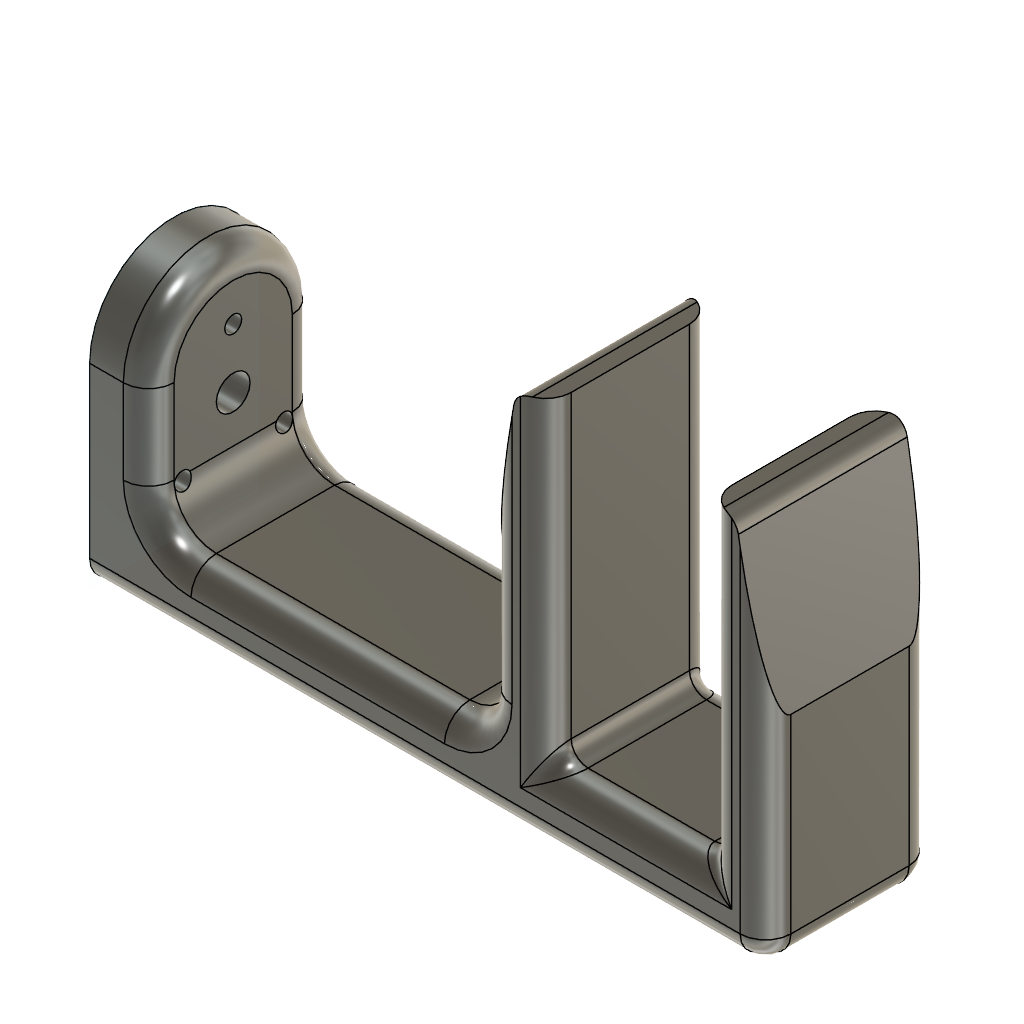
24mce1012_doorstop_model (Autodesk Fusion 360 design; units mm, degrees)
part number: 2026-11-01-15-57-34-278
Autodesk Fusion 360 part; units mm, degrees
sketch "Sketch1" plane through (0, 0, 0) normal (0, 0, 1) x (1, 0, 0)
  line L0 (80, 20) -> (-80, 20)
  line L1 (-80, 20) -> (-80, -20)
  line L2 (-80, -20) -> (80, -20)
  line L3 (80, -20) -> (80, 20)
  line L4 (80, 20) -> (-80, -20) construction
  line L5 (-80, 20) -> (80, -20) construction
  dimension "d1" = 40
  dimension "d2" = 160
  constraint horizontal L0
  constraint perpendicular L0 L1
  constraint parallel L0 L2
  constraint parallel L1 L3
  constraint coincident L4 origin
  constraint coincident L5 origin
  measures "d1" distance of L0.end L1.end
  measures "d2" distance of L0.start L0.end
extrude "Extrude1" add sketch "Sketch1" along normal blind 16
sketch "Sketch2" plane through (-80, 0, 0) normal (-1, 0, 0) x (0, -1, 0)
  line L0 (-20, 0) -> (20, 0)
  line L1 (20, 0) -> (20, 16)
  line L2 (20, 16) -> (-20, 16)
  line L3 (-20, 16) -> (-20, 0)
  line L4 (-20, 16) -> (-20, 46)
  line L5 (-20, 16) -> (20, 16)
  line L6 (20, 16) -> (20, 46)
  arc A0 (20, 46) -> (-20, 46) centre (0, 46) ccw
  dimension "d5" = 30
  constraint coincident L2.end L3.start
  constraint perpendicular L2 L4
  constraint coincident L1.end L2.start
  constraint perpendicular L2 L6
  measures "d5" distance of L2.end L4.end
extrude "Extrude2" add sketch "Sketch2" against normal blind 14 contours L2 L4 L5 L6 A0
sketch "Sketch3" plane through (80, 0, 0) normal (1, 0, 0) x (0, 1, 0)
  line L0 (-20, 0) -> (20, 0)
  line L1 (20, 0) -> (20, 16)
  line L2 (20, 16) -> (-20, 16)
  line L3 (-20, 16) -> (-20, 0)
  line L4 (-20, 16) -> (20, 16)
  line L5 (20, 16) -> (20, 91)
  line L6 (20, 91) -> (-20, 91)
  line L7 (-20, 91) -> (-20, 16)
  dimension "d8" = 75
  constraint coincident L2.end L3.start
  constraint coincident L1.end L2.start
  constraint perpendicular L2 L5
  constraint perpendicular L3 L6
  constraint perpendicular L2 L7
  measures "d8" distance of L1.end L5.end
extrude "Extrude3" add sketch "Sketch3" against normal blind 14 contours L2 L4 L5 L6 L7
sketch "Sketch4" plane through (0, 0, 16) normal (0, 0, 1) x (-1, 0, 0)
  line L0 (-66, 20) -> (-66, -20)
  line L1 (-66, -20) -> (66, -20)
  line L2 (66, -20) -> (66, 20)
  line L3 (66, 20) -> (-66, 20)
  line L4 (-66, -20) -> (-28, -20)
  line L5 (-28, -20) -> (-28, 20)
  line L6 (-28, 20) -> (-14, 20)
  line L7 (-14, 20) -> (-14, -20)
  line L8 (-28, -20) -> (-14, -20)
  dimension "d11" = 38
  dimension "d12" = 14
  constraint coincident L0.end L1.start
  constraint perpendicular L0 L4
  constraint coincident L3 L5.end
  constraint perpendicular L3 L5
  constraint perpendicular L5 L6
  constraint coincident L1 L7.end
  constraint perpendicular L1 L7
  measures "d11" distance of L0.end L4.end
  measures "d12" distance of L5.end L6.end
extrude "Extrude4" add sketch "Sketch4" along normal blind 75 contours L1 L3 L5 L6 L7 L8
sketch "Sketch5" plane through (0, -20, 0) normal (0, -1, 0) x (1, 0, 0)
  line L0 (-80, 0) -> (80, 0)
  line L1 (80, 0) -> (80, 91)
  line L2 (80, 91) -> (66, 91)
  line L3 (66, 91) -> (66, 16)
  line L4 (66, 16) -> (28, 16)
  line L5 (28, 16) -> (28, 91)
  line L6 (28, 91) -> (14, 91)
  line L7 (14, 91) -> (14, 16)
  line L8 (14, 16) -> (-66, 16)
  line L9 (-66, 16) -> (-66, 46)
  line L10 (-66, 46) -> (-80, 46)
  line L11 (-80, 46) -> (-80, 0)
  line L12 (28, 91) -> (21, 91)
  line L13 (21, 91) -> (21, 51)
  line L14 (21, 51) -> (14, 51)
  line L15 (14, 51) -> (21, 91)
  line L16 (21, 51) -> (73, 51)
  line L17 (73, 51) -> (47, 51)
  line L18 (47, 51) -> (47, 80)
  line L19 (80, 51) -> (73, 91)
  line L20 (73, 51) -> (80, 51)
  line L21 (73, 91) -> (73, 51)
  line L22 (47, 51) -> (47, 80)
  constraint coincident L5.end L6.start
  constraint midpoint L6 L12.end
  constraint perpendicular L6 L13
  constraint coincident L7 L14.end
  constraint perpendicular L7 L14
  constraint perpendicular L1 L16
  constraint midpoint L16 L17.end
  constraint perpendicular L17 L18
  constraint symmetric L12.end L18 L19.end
  constraint symmetric L13.end L18 L16.end
  constraint symmetric L14.end L18 L19.start
  constraint symmetric L17.end L18 L22.start
  constraint symmetric L22.end L18 L18.end
extrude "Extrude5" cut sketch "Sketch5" against normal blind 100 contours L1 L2 L19 | L6 L7 L15
fillet "Fillet1" radius 10 1 edges at (14, 0, 16)
fillet "Fillet2" radius 10 1 edges at (-66, 0, 16)
sketch "Sketch6" plane through (-80, 0, 0) normal (-1, 0, 0) x (0, -1, 0)
  line L0 (-20, 0) -> (20, 0)
  line L1 (20, 0) -> (20, 46)
  arc A0 (20, 46) -> (-20, 46) centre (0, 46) ccw
  line L2 (-20, 46) -> (-20, 0)
sketch "Sketch7" plane through (-80, 0, 0) normal (-1, 0, 0) x (0, -1, 0)
sketch "Sketch8" plane through (-80, 0, 0) normal (-1, 0, 0) x (0, -1, 0)
  line L0 (-20, 0) -> (-20, 16)
  line L1 (-20, 16) -> (20, 16)
  line L2 (0, 16) -> (0, 51)
  circle A0 centre (0, 51) radius 2
  line L3 (0, 25) -> (-12, 25)
  circle A1 centre (-12, 25) radius 2
  circle A2 centre (12, 25) radius 2
  dimension "d21" = 16
  dimension "d22" = 35
  dimension "d23" = 4
  dimension "d24" = 12
  dimension "d25" = 4
  constraint vertical L0
  constraint perpendicular L0 L1
  constraint midpoint L1 L2.start
  constraint perpendicular L1 L2
  constraint coincident L2.end A0.centre
  constraint coincident L2 L3.start
  constraint perpendicular L2 L3
  constraint coincident L3.end A1.centre
  constraint symmetric L2 A1 A2
  measures "d21" distance of L0.start L0.end
  measures "d22" distance of L2.start L2.end
  measures "d23" diameter of A0
  measures "d24" distance of L3.start L3.end
  measures "d25" diameter of A1
extrude "Extrude6" cut sketch "Sketch8" against normal blind 20
fillet "Fillet3" radius 6 11 edges at (14, 20, 38.5) (11.0711, 20, 18.9289) (-26, 20, 16) (-63.0711, 20, 18.9289) (-66, 20, 36) (-66, 0, 66) (-66, -20, 36) (-63.0711, -20, 18.9289) (-26, -20, 16) (11.0711, -20, 18.9289) (14, -20, 38.5)
fillet "Fillet4" radius 6 3 edges at (0, -20, 0) (0, 20, 0) (80, 0, 0)
fillet "Fillet5" radius 6 2 edges at (47, -20, 16) (47, 20, 16)
fillet "Fillet6" radius 6 4 edges at (28, 20, 50.5) (28, -20, 50.5) (66, 20, 50.5) (66, -20, 50.5)
fillet "Fillet7" radius 6 4 edges at (78.2426, -18.2426, 1.7574) (80, -20, 28.5) (78.2426, 18.2426, 1.7574) (80, 20, 28.5)
fillet "Fillet8" radius 4 2 edges at (73, 0, 91) (21, 0, 91)
fillet "Fillet9" radius 4 6 edges at (67.7574, -18.2426, 14.2426) (66, 0, 16) (67.7574, 18.2426, 14.2426) (26.2426, 18.2426, 14.2426) (28, 0, 16) (26.2426, -18.2426, 14.2426)
sketch "Sketch9" plane through (-80, 0, 0) normal (-1, 0, 0) x (0, -1, 0)
  circle A0 centre (0, 37) radius 4
  dimension "d42" = 8
  measures "d42" diameter of A0
extrude "Extrude7" cut sketch "Sketch9" against normal blind 20
